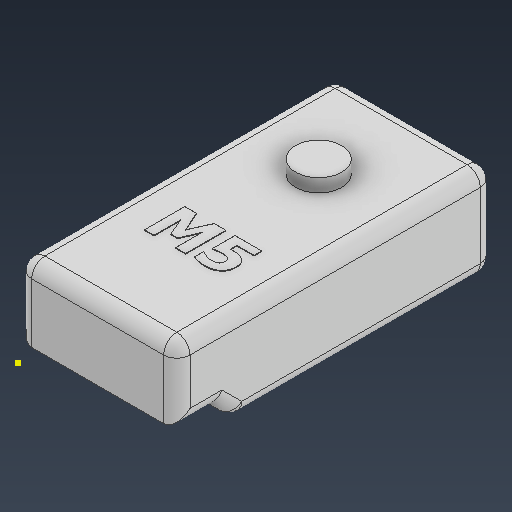
# Autodesk Inventor part: forenkla
Saved by Autodesk Inventor 2027.1 (Build 311270010, 270A)
## iProperties
Created: 2026-09-17
Part Number: forenkla
Material: Generic
Document SubType Name: Modeling
Designer: evenb
Density: 1 g/cm^3
Appearance: Default
Author: evenb
Autodesk Inventor part; units mm, degrees
ref_plane "YZ Plane" through (0, 0, 0) normal (1, 0, 0) x (0, 1, 0)
ref_plane "XZ Plane" through (0, 0, 0) normal (0, 1, 0) x (-1, 0, 0)
ref_plane "XY Plane" through (0, 0, 0) normal (0, 0, 1) x (1, 0, 0)
sketch "Sketch1" plane through (0, 0, 0) normal (0, 1, 0) x (-1, 0, 0)
  line L0 (0, 0) -> (-24, 0)
  line L1 (-24, 0) -> (-24, -48)
  line L2 (-24, -48) -> (0, -48)
  line L3 (0, -48) -> (0, 0)
  dimension "d0" = 24
  dimension "d1" = 48
  constraints: 8 end point, 2 parallel, 1 horizontal, 1 perpendicular
  measures "d0" distance of L2.end L1.end
  measures "d1" distance of L1.end L0.end
extrude "Extrusion1" add sketch "Sketch1" along normal blind 14
sketch "Sketch2" plane through (24, 0, 0) normal (1, 0, 0) x (0, 0, -1)
  line L0 (0, 0) -> (0, 3)
  line L1 (0, 0) -> (0, 14) projected
  line L2 (0, 3) -> (6, 3)
  line L3 (0, 0) -> (9, 0)
  line L4 (0, 0) -> (48, 0) projected
  line L5 (9, 0) -> (6, 3)
  dimension "d4" = 3
  dimension "d5" = 6
  dimension "d6" = 9
  constraints: 8 end point, 2 point on line, 1 perpendicular
  measures "d4" distance of L0.start L0.end
  measures "d5" distance of L0.end L2.end
  measures "d6" distance of L0.start L3.end
extrude "Extrusion2" cut sketch "Sketch2" against normal up to surface (24 mm away)
sketch "Sketch3" plane through (0, 14, 0) normal (0, 1, 0) x (1, 0, 0)
  circle A0 centre (12, 33.5) radius 3.5
  line L0 (24, 48) -> (0, 48) projected
  point P0 (0, 0)
  dimension "d9" = 7
  dimension "d10" = 14.5
  constraints: 1 centre point
  measures "d9" diameter of A0
  measures "d10" distance from line of L0 A0.centre
extrude "Extrusion3" add sketch "Sketch3" along normal blind 2
sketch "Sketch4" plane through (0, 14, 0) normal (0, 1, 0) x (1, 0, 0)
  line L0 (5.5768, 18.9977) -> (11.0949, 18.9977) construction
  line L1 (11.0949, 18.9977) -> (11.0949, 15.8854) construction
  line L2 (11.0949, 15.8854) -> (5.5768, 15.8854) construction
  line L3 (5.5768, 15.8854) -> (5.5768, 18.9977) construction
  line L4 (24, 0) -> (24, 48) projected
  line L5 (12.4336, 12.9017) -> (10.9121, 12.9017)
  line L6 (10.9121, 12.9017) -> (10.9121, 16.9426)
  line L7 (10.9121, 16.9426) -> (9.8055, 14.3343)
  line L8 (9.8055, 14.3343) -> (8.7582, 14.3343)
  line L9 (8.7582, 14.3343) -> (7.6517, 16.9426)
  line L10 (7.6517, 16.9426) -> (7.6517, 12.9017)
  line L11 (7.6517, 12.9017) -> (6.2092, 12.9017)
  line L12 (6.2092, 12.9017) -> (6.2092, 18.9977)
  line L13 (6.2092, 18.9977) -> (7.9728, 18.9977)
  line L14 (7.9728, 18.9977) -> (9.3263, 15.9892)
  line L15 (9.3263, 15.9892) -> (10.67, 18.9977)
  line L16 (10.67, 18.9977) -> (12.4336, 18.9977)
  line L17 (12.4336, 18.9977) -> (12.4336, 12.9017)
  spline S0 degree 2 poles (18.0257, 14.9666) (18.0257, 14.4874) (17.6997, 13.6772) (17.3786, 13.3858) knots 0 0 0 1 2 2 2
  spline S1 degree 2 poles (17.3786, 13.3858) (17.0575, 13.0943) (16.1781, 12.7732) (15.5359, 12.7732) knots 0 0 0 1 2 2 2
  spline S2 degree 2 poles (15.5359, 12.7732) (14.8542, 12.7782) (13.8761, 13.0005) (13.555, 13.1437) knots 0 0 0 1 2 2 2
  line L18 (13.555, 13.1437) -> (13.555, 14.4726)
  line L19 (13.555, 14.4726) -> (13.6933, 14.4726)
  spline S3 degree 2 poles (13.6933, 14.4726) (13.8119, 14.4084) (14.0984, 14.2404) (14.3306, 14.1515) knots 0 0 0 1 2 2 2
  spline S4 degree 2 poles (14.3306, 14.1515) (14.5479, 14.0675) (14.9975, 13.9539) (15.2692, 13.9539) knots 0 0 0 1 2 2 2
  spline S5 degree 2 poles (15.2692, 13.9539) (15.5063, 13.9539) (16.0596, 14.0724) (16.2275, 14.2305) knots 0 0 0 1 2 2 2
  spline S6 degree 2 poles (16.2275, 14.2305) (16.351, 14.354) (16.4894, 14.6554) (16.4894, 14.9073) knots 0 0 0 1 2 2 2
  spline S7 degree 2 poles (16.4894, 14.9073) (16.4894, 15.1247) (16.3115, 15.431) (16.1683, 15.5248) knots 0 0 0 1 2 2 2
  spline S8 degree 2 poles (16.1683, 15.5248) (15.9608, 15.6631) (15.368, 15.7422) (15.1556, 15.7422) knots 0 0 0 1 2 2 2
  spline S9 degree 2 poles (15.1556, 15.7422) (14.8196, 15.7422) (14.1824, 15.6335) (13.9502, 15.5742) knots 0 0 0 1 2 2 2
  line L20 (13.9502, 15.5742) -> (13.8168, 15.5742)
  line L21 (13.8168, 15.5742) -> (13.8168, 18.9977)
  line L22 (13.8168, 18.9977) -> (17.8578, 18.9977)
  line L23 (17.8578, 18.9977) -> (17.8578, 17.8466)
  line L24 (17.8578, 17.8466) -> (15.2642, 17.8466)
  line L25 (15.2642, 17.8466) -> (15.2642, 16.8339)
  spline S10 degree 2 poles (15.2642, 16.8339) (15.3877, 16.8438) (15.7286, 16.8537) (15.8225, 16.8537) knots 0 0 0 1 2 2 2
  spline S11 degree 2 poles (15.8225, 16.8537) (16.2621, 16.8537) (17.0031, 16.6758) (17.2946, 16.4931) knots 0 0 0 1 2 2 2
  spline S12 degree 2 poles (17.2946, 16.4931) (17.6404, 16.2658) (18.0257, 15.51) (18.0257, 14.9666) knots 0 0 0 1 2 2 2
  point P0 (0, 0)
  point P1 (11.0949, 17.4415)
  dimension "d13" = 12.9052
  constraints: 1 midpoint, 2 other
  measures "d13" distance from line of L4 point (11.095, 17.442)
extrude "Extrusion4" add sketch "Sketch4" along normal blind 0.1
sketch "Sketch5" plane through (0, 14, 0) normal (0, 0, 1) x (1, 0, 0)
  point P0 (0, -14)
fillet "Fillet1" radius 2 16 edges at (0, 7, -48) (24, 7, -48) (24, 8.5, 0) (0, 8.5, 0) (0, 14, -24) (0, 0, -28.5) (0, 1.5, -7.5) (0, 3, -3) (24, 3, -3) (24, 1.5, -7.5) (24, 0, -28.5) (24, 14, -24) (12, 14, -48) (12, 0, -48) (12, 14, 0) (12, 0, -9)
body "Solid1"
